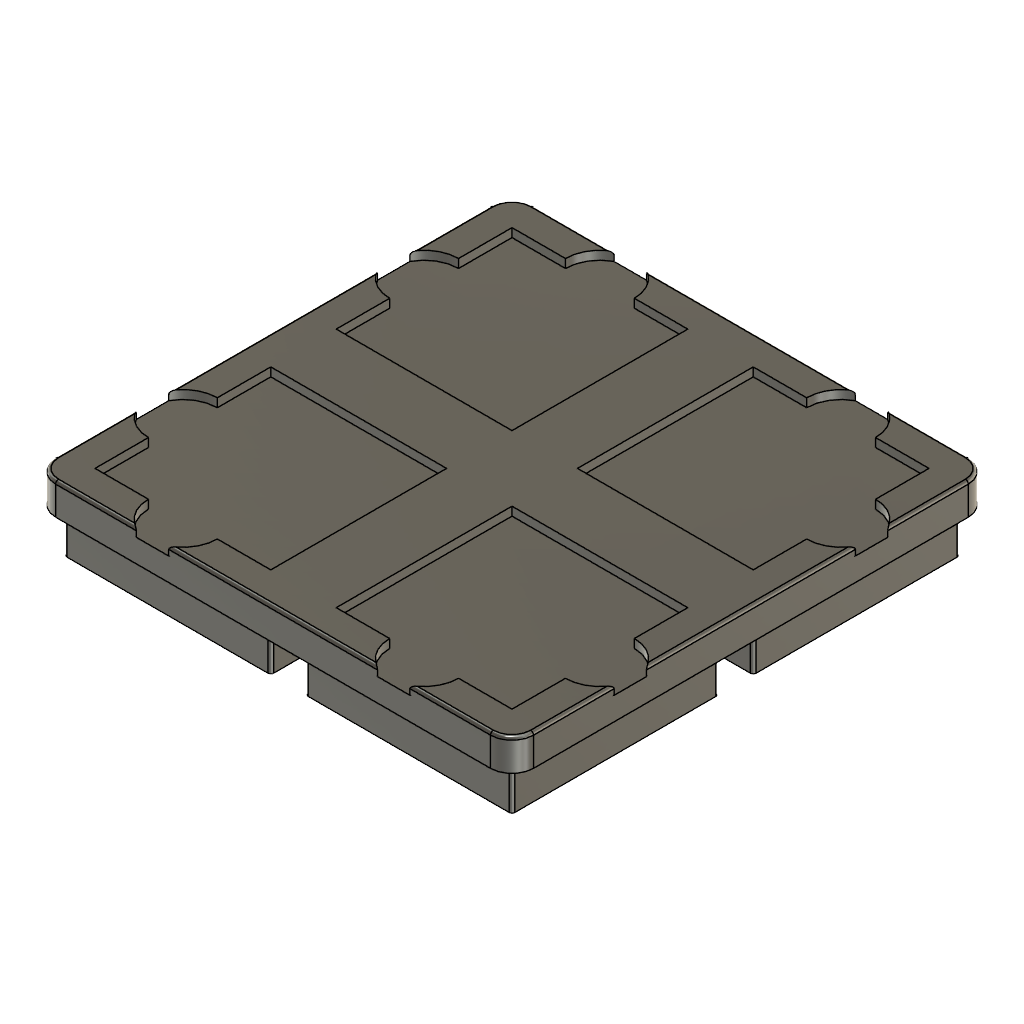
glass-input-holder-v1 (Autodesk Fusion 360 design; units mm, degrees)
part number: 2026-10-03-11-57-42-661
Autodesk Fusion 360 part; units mm, degrees
sketch "Sketch_OuterProfile" plane through (0, 0, 0) normal (0, 0, 1) x (1, 0, 0)
  line L0 (41.6, 41.6) -> (-41.6, 41.6)
  line L1 (-41.6, 41.6) -> (-41.6, -41.6)
  line L2 (-41.6, -41.6) -> (41.6, -41.6)
  line L3 (41.6, -41.6) -> (41.6, 41.6)
  dimension "d26" = 83.2
  dimension "d27" = 83.2
  measures "d26" horizontal distance of L0.start L0.end
  measures "d27" vertical distance of L0.end L1.end
extrude "Extrude_Body" add sketch "Sketch_OuterProfile" along normal blind 5.5
fillet "Fillet_OuterVerticalEdges" radius 3.75 4 edges at (41.6, -41.6, 2.75) (-41.6, -41.6, 2.75) (-41.6, 41.6, 2.75) (41.6, 41.6, 2.75)
fillet "Fillet_TopOuterEdge" radius 0.5 64 edges at (40.5017, 40.5017, 5.5) (41.6, 0, 5.5) (40.5017, -40.5017, 5.5) (0, -41.6, 5.5) (-40.5017, -40.5017, 5.5) (-41.6, 0, 5.5) (-40.5017, 40.5017, 5.5) (0, 41.6, 5.5) (0, 41.6, 5.5) (-40.5017, 40.5017, 5.5) (-41.6, 0, 5.5) (-40.5017, -40.5017, 5.5) (0, -41.6, 5.5) (40.5017, -40.5017, 5.5) (41.6, 0, 5.5) (40.5017, 40.5017, 5.5) (-40.5017, 40.5017, 5.5) (0, 41.6, 5.5) (40.5017, 40.5017, 5.5) (41.6, 0, 5.5) (40.5017, -40.5017, 5.5) (0, -41.6, 5.5) (-40.5017, -40.5017, 5.5) (-41.6, 0, 5.5) (-41.6, 0, 5.5) (-40.5017, -40.5017, 5.5) (0, -41.6, 5.5) (40.5017, -40.5017, 5.5) (41.6, 0, 5.5) (40.5017, 40.5017, 5.5) (0, 41.6, 5.5) (-40.5017, 40.5017, 5.5) (-40.5017, -40.5017, 5.5) (-41.6, 0, 5.5) (-40.5017, 40.5017, 5.5) (0, 41.6, 5.5) (40.5017, 40.5017, 5.5) (41.6, 0, 5.5) (40.5017, -40.5017, 5.5) (0, -41.6, 5.5) (0, -41.6, 5.5) (40.5017, -40.5017, 5.5) (41.6, 0, 5.5) (40.5017, 40.5017, 5.5) (0, 41.6, 5.5) (-40.5017, 40.5017, 5.5) (-41.6, 0, 5.5) (-40.5017, -40.5017, 5.5) (40.5017, -40.5017, 5.5) (0, -41.6, 5.5) (-40.5017, -40.5017, 5.5) (-41.6, 0, 5.5) (-40.5017, 40.5017, 5.5) (0, 41.6, 5.5) (40.5017, 40.5017, 5.5) (41.6, 0, 5.5) (41.6, 0, 5.5) (40.5017, 40.5017, 5.5) (0, 41.6, 5.5) (-40.5017, 40.5017, 5.5) (-41.6, 0, 5.5) (-40.5017, -40.5017, 5.5) (0, -41.6, 5.5) (40.5017, -40.5017, 5.5)
ref_plane "WorkPlane1" through (0, 0, 5.5) normal (0, 0, 1) x (1, 0, 0)
sketch "Sketch_Pocket_1" plane through (0, 0, 5.5) normal (0, 0, 1) x (1, 0, 0)
  line L0 (-5.7, -5.7) -> (-36.3, -5.7)
  line L1 (-36.3, -5.7) -> (-36.3, -36.3)
  line L2 (-36.3, -36.3) -> (-5.7, -36.3)
  line L3 (-5.7, -36.3) -> (-5.7, -5.7)
  dimension "d37" = 30.6
  dimension "d38" = 30.6
  measures "d37" horizontal distance of L0.start L0.end
  measures "d38" vertical distance of L0.end L1.end
extrude "Extrude_Pocket_1" cut sketch "Sketch_Pocket_1" against normal blind 1.5
sketch "Sketch_FingerAccessX_1" plane through (0, 0, 5.5) normal (0, 0, 1) x (1, 0, 0)
  circle A0 centre (-36.3, -21) radius 6
extrude "Extrude_FingerAccessX_1" cut sketch "Sketch_FingerAccessX_1" against normal blind 1.5
sketch "Sketch_FingerAccessY_1" plane through (0, 0, 5.5) normal (0, 0, 1) x (1, 0, 0)
  circle A0 centre (-21, -36.3) radius 6
extrude "Extrude_FingerAccessY_1" cut sketch "Sketch_FingerAccessY_1" against normal blind 1.5
sketch "Sketch_Pocket_2" plane through (0, 0, 5.5) normal (0, 0, 1) x (1, 0, 0)
  line L0 (-5.7, 36.3) -> (-36.3, 36.3)
  line L1 (-36.3, 36.3) -> (-36.3, 5.7)
  line L2 (-36.3, 5.7) -> (-5.7, 5.7)
  line L3 (-5.7, 5.7) -> (-5.7, 36.3)
  dimension "d45" = 30.6
  dimension "d46" = 30.6
  measures "d45" horizontal distance of L0.start L0.end
  measures "d46" vertical distance of L0.end L1.end
extrude "Extrude_Pocket_2" cut sketch "Sketch_Pocket_2" against normal blind 1.5
sketch "Sketch_FingerAccessX_2" plane through (0, 0, 5.5) normal (0, 0, 1) x (1, 0, 0)
  circle A0 centre (-36.3, 21) radius 6
extrude "Extrude_FingerAccessX_2" cut sketch "Sketch_FingerAccessX_2" against normal blind 1.5
sketch "Sketch_FingerAccessY_2" plane through (0, 0, 5.5) normal (0, 0, 1) x (1, 0, 0)
  circle A0 centre (-21, 36.3) radius 6
extrude "Extrude_FingerAccessY_2" cut sketch "Sketch_FingerAccessY_2" against normal blind 1.5
sketch "Sketch_Pocket_3" plane through (0, 0, 5.5) normal (0, 0, 1) x (1, 0, 0)
  line L0 (36.3, -5.7) -> (5.7, -5.7)
  line L1 (5.7, -5.7) -> (5.7, -36.3)
  line L2 (5.7, -36.3) -> (36.3, -36.3)
  line L3 (36.3, -36.3) -> (36.3, -5.7)
  dimension "d53" = 30.6
  dimension "d54" = 30.6
  measures "d53" horizontal distance of L0.start L0.end
  measures "d54" vertical distance of L0.end L1.end
extrude "Extrude_Pocket_3" cut sketch "Sketch_Pocket_3" against normal blind 1.5
sketch "Sketch_FingerAccessX_3" plane through (0, 0, 5.5) normal (0, 0, 1) x (1, 0, 0)
  circle A0 centre (36.3, -21) radius 6
extrude "Extrude_FingerAccessX_3" cut sketch "Sketch_FingerAccessX_3" against normal blind 1.5
sketch "Sketch_FingerAccessY_3" plane through (0, 0, 5.5) normal (0, 0, 1) x (1, 0, 0)
  circle A0 centre (21, -36.3) radius 6
extrude "Extrude_FingerAccessY_3" cut sketch "Sketch_FingerAccessY_3" against normal blind 1.5
sketch "Sketch_Pocket_4" plane through (0, 0, 5.5) normal (0, 0, 1) x (1, 0, 0)
  line L0 (36.3, 36.3) -> (5.7, 36.3)
  line L1 (5.7, 36.3) -> (5.7, 5.7)
  line L2 (5.7, 5.7) -> (36.3, 5.7)
  line L3 (36.3, 5.7) -> (36.3, 36.3)
  dimension "d61" = 30.6
  dimension "d62" = 30.6
  measures "d61" horizontal distance of L0.start L0.end
  measures "d62" vertical distance of L0.end L1.end
extrude "Extrude_Pocket_4" cut sketch "Sketch_Pocket_4" against normal blind 1.5
sketch "Sketch_FingerAccessX_4" plane through (0, 0, 5.5) normal (0, 0, 1) x (1, 0, 0)
  circle A0 centre (36.3, 21) radius 6
extrude "Extrude_FingerAccessX_4" cut sketch "Sketch_FingerAccessX_4" against normal blind 1.5
sketch "Sketch_FingerAccessY_4" plane through (0, 0, 5.5) normal (0, 0, 1) x (1, 0, 0)
  circle A0 centre (21, 36.3) radius 6
extrude "Extrude_FingerAccessY_4" cut sketch "Sketch_FingerAccessY_4" against normal blind 1.5
sketch "Sketch_Foot_1" plane through (0, 0, 0) normal (0, 0, 1) x (1, 0, 0)
  line L0 (-3.01, -3.01) -> (-38.99, -3.01)
  line L1 (-38.99, -3.01) -> (-38.99, -38.99)
  line L2 (-38.99, -38.99) -> (-3.01, -38.99)
  line L3 (-3.01, -38.99) -> (-3.01, -3.01)
  dimension "d77" = 35.98
  dimension "d78" = 35.98
  measures "d77" horizontal distance of L0.start L0.end
  measures "d78" vertical distance of L0.end L1.end
extrude "Extrude_Foot_1" add sketch "Sketch_Foot_1" against normal blind 4.65
fillet "Fillet_FootEdges_1" radius 0.5 4 edges at (-3.01, -3.01, -2.325) (-38.99, -3.01, -2.325) (-38.99, -38.99, -2.325) (-3.01, -38.99, -2.325)
sketch "Sketch_Foot_2" plane through (0, 0, 0) normal (0, 0, 1) x (1, 0, 0)
  line L0 (-3.01, 38.99) -> (-38.99, 38.99)
  line L1 (-38.99, 38.99) -> (-38.99, 3.01)
  line L2 (-38.99, 3.01) -> (-3.01, 3.01)
  line L3 (-3.01, 3.01) -> (-3.01, 38.99)
  dimension "d83" = 35.98
  dimension "d84" = 35.98
  measures "d83" horizontal distance of L0.start L0.end
  measures "d84" vertical distance of L0.end L1.end
extrude "Extrude_Foot_2" add sketch "Sketch_Foot_2" against normal blind 4.65
fillet "Fillet_FootEdges_2" radius 0.5 4 edges at (-3.01, 38.99, -2.325) (-38.99, 38.99, -2.325) (-38.99, 3.01, -2.325) (-3.01, 3.01, -2.325)
sketch "Sketch_Foot_3" plane through (0, 0, 0) normal (0, 0, 1) x (1, 0, 0)
  line L0 (38.99, -3.01) -> (3.01, -3.01)
  line L1 (3.01, -3.01) -> (3.01, -38.99)
  line L2 (3.01, -38.99) -> (38.99, -38.99)
  line L3 (38.99, -38.99) -> (38.99, -3.01)
  dimension "d89" = 35.98
  dimension "d90" = 35.98
  measures "d89" horizontal distance of L0.start L0.end
  measures "d90" vertical distance of L0.end L1.end
extrude "Extrude_Foot_3" add sketch "Sketch_Foot_3" against normal blind 4.65
fillet "Fillet_FootEdges_3" radius 0.5 4 edges at (38.99, -3.01, -2.325) (3.01, -3.01, -2.325) (3.01, -38.99, -2.325) (38.99, -38.99, -2.325)
sketch "Sketch_Foot_4" plane through (0, 0, 0) normal (0, 0, 1) x (1, 0, 0)
  line L0 (38.99, 38.99) -> (3.01, 38.99)
  line L1 (3.01, 38.99) -> (3.01, 3.01)
  line L2 (3.01, 3.01) -> (38.99, 3.01)
  line L3 (38.99, 3.01) -> (38.99, 38.99)
  dimension "d95" = 35.98
  dimension "d96" = 35.98
  measures "d95" horizontal distance of L0.start L0.end
  measures "d96" vertical distance of L0.end L1.end
extrude "Extrude_Foot_4" add sketch "Sketch_Foot_4" against normal blind 4.65
fillet "Fillet_FootEdges_4" radius 0.5 4 edges at (38.99, 38.99, -2.325) (3.01, 38.99, -2.325) (3.01, 3.01, -2.325) (38.99, 3.01, -2.325)
extrude "Extrude18" add 4 faces at (-15.17, -26.9967, -4.65) (-26.83, 15.0033, -4.65) (15.17, 15.3367, -4.65) (15.3367, -26.83, -4.65) along direction (0, 0, -1) blind 3
equation "grid_pitch = 42 mm" comment "Gridfinity grid pitch (standard, per MG400 rig doc)"
equation "grid_clearance = 0.3 mm" comment "Fit clearance measured in Lab 1 (range 0.2-0.4 mm, chosen 0.3 mm)"
equation "gf_outer_offset = 0.5 mm" comment "Standard Gridfinity outer undersize per cell (42n - 0.5)"
equation "gf_corner_radius = 3.75 mm" comment "Standard Gridfinity outer vertical corner radius"
equation "gf_foot_chamfer_bottom = 0.8 mm" comment "Gridfinity foot: bottom 45deg segment height (reference)"
equation "gf_foot_vertical = 1.8 mm" comment "Gridfinity foot: vertical segment height (reference)"
equation "gf_foot_chamfer_top = 2.15 mm" comment "Gridfinity foot: top 45deg segment height (reference)"
equation "foot_lead_in_chamfer = gf_foot_chamfer_bottom + gf_foot_chamfer_top" comment "Simplified single lead-in chamfer approximating the Gridfinity foot flare"
equation "grid_cols = 2" comment "Number of Gridfinity cells in X (build-time layout parameter)"
equation "grid_rows = 2" comment "Number of Gridfinity cells in Y (build-time layout parameter)"
equation "glass_width = 30 mm" comment "Polycarbonate glass piece width (given)"
equation "glass_length = 30 mm" comment "Polycarbonate glass piece length (given)"
equation "glass_thickness = 2 mm" comment "Polycarbonate glass piece thickness (given)"
equation "part_clearance = 0.3 mm" comment "Printer fit clearance measured in Lab 1, applied per side between glass and pocket"
equation "pocket_width = glass_width + 2 * part_clearance" comment "Pocket opening width (glass width plus clearance both sides)"
equation "pocket_length = glass_length + 2 * part_clearance" comment "Pocket opening length (glass length plus clearance both sides)"
equation "reveal_height = 0.5 mm" comment "ASSUMPTION: how far the glass protrudes above the holder top surface for suction-cup and finger access"
equation "pocket_depth = glass_thickness - reveal_height" comment "Pocket depth, kept shallow so the glass top stays exposed"
equation "floor_thickness = 4 mm" comment "ASSUMPTION: solid floor thickness beneath the pocket"
equation "holder_height = pocket_depth + floor_thickness" comment "Total external height of the holder (kept low, no high walls)"
equation "holder_outer_x = grid_pitch * grid_cols - gf_outer_offset - grid_clearance" comment "Outer footprint in X, derived from cell count"
equation "holder_outer_y = grid_pitch * grid_rows - gf_outer_offset - grid_clearance" comment "Outer footprint in Y, derived from cell count"
equation "lead_in_chamfer = 0.5 mm" comment "ASSUMPTION: small chamfer around each pocket opening to ease glass insertion (reduced size for this thin, shallow tray)"
equation "top_edge_fillet_radius = 0.5 mm" comment "ASSUMPTION: small deburr fillet on the top outer rim (reduced from standard Gridfinity radius since this part is very thin)"
equation "finger_cutout_radius = 6 mm" comment "ASSUMPTION: radius of the finger-access scallop cut into two outward-facing sides of each pocket"
equation "d26 = holder_outer_x"
equation "d27 = holder_outer_y"
equation "d28 = holder_height"
equation "d31 = gf_corner_radius"
equation "d34 = top_edge_fillet_radius"
equation "d35 = holder_height"
equation "d37 = pocket_width"
equation "d38 = pocket_length"
equation "d39 = -pocket_depth"
equation "d41 = -pocket_depth"
equation "d43 = -pocket_depth"
equation "d45 = pocket_width"
equation "d46 = pocket_length"
equation "d47 = -pocket_depth"
equation "d49 = -pocket_depth"
equation "d51 = -pocket_depth"
equation "d53 = pocket_width"
equation "d54 = pocket_length"
equation "d55 = -pocket_depth"
equation "d57 = -pocket_depth"
equation "d59 = -pocket_depth"
equation "d61 = pocket_width"
equation "d62 = pocket_length"
equation "d63 = -pocket_depth"
equation "d65 = -pocket_depth"
equation "d67 = -pocket_depth"
equation "gf_socket_mouth_size = 41.98 mm" comment "MEASURED from MG400 rakis grid_pos_0: top opening of real baseplate socket"
equation "gf_socket_mid_size = 37.68 mm" comment "MEASURED: socket width after top chamfer segment"
equation "gf_socket_floor_size = 36.28 mm" comment "MEASURED: narrowest width at socket floor"
equation "gf_socket_depth = 4.65 mm" comment "MEASURED: real socket depth (0.70 + 1.80 + 2.15 mm segments), corrects earlier 4.75 mm assumption"
equation "foot_size = gf_socket_floor_size - grid_clearance" comment "Simplified constant-width foot sized to the socket floor (narrowest, guaranteed-fit) minus clearance"
equation "foot_depth = gf_socket_depth" comment "Foot protrusion depth below the main floor, matches measured socket depth"
equation "foot_corner_radius = 0.5 mm" comment "MEASURED (approx): real socket corner radius near its narrowest point"
equation "total_height_with_feet = holder_height + foot_depth" comment "Overall height including protruding feet, for reference"
equation "d77 = foot_size"
equation "d78 = foot_size"
equation "d79 = -foot_depth"
equation "d82 = foot_corner_radius"
equation "d83 = foot_size"
equation "d84 = foot_size"
equation "d85 = -foot_depth"
equation "d88 = foot_corner_radius"
equation "d89 = foot_size"
equation "d90 = foot_size"
equation "d91 = -foot_depth"
equation "d94 = foot_corner_radius"
equation "d95 = foot_size"
equation "d96 = foot_size"
equation "d97 = -foot_depth"
equation "d100 = foot_corner_radius"
named bodies: "GlassHolderBody"
